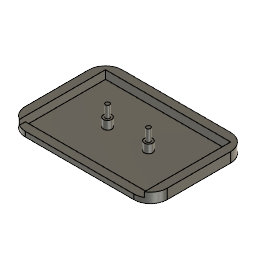
Battery holder cover (Autodesk Fusion 360 design; units mm, degrees)
Autodesk Fusion 360 part; units mm, degrees
sketch "Sketch1" plane through (0, 0, 0) normal (0, 0, 1) x (1, 0, 0)
  line L0 (0, 0) -> (85, 0)
  line L1 (85, 0) -> (85, 58)
  line L2 (85, 58) -> (0, 58)
  line L3 (0, 58) -> (0, 0)
  dimension "d1" = 85
  dimension "d2" = 58
  constraint horizontal L0
  constraint vertical L1
  constraint horizontal L2
  constraint vertical L3
  constraint coincident L0.start L3.end
  measures "d1" distance of L0.start L0.end
  measures "d2" distance of L0.start L2.end
extrude "Extrude1" add sketch "Sketch1" along normal blind 1
fillet "Fillet1" radius 10 4 edges at (85, 0, 0.5) (0, 0, 0.5) (0, 58, 0.5) (85, 58, 0.5)
sketch "Sketch2" plane through (0, 0, 1) normal (0, 0, 1) x (-1, 0, 0)
  arc A0 (-85, -48) -> (-75, -58) centre (-75, -48) ccw
  line L0 (-75, -58) -> (-10, -58)
  arc A1 (-10, -58) -> (0, -48) centre (-10, -48) ccw
  line L1 (0, -48) -> (0, -10)
  arc A2 (0, -10) -> (-10, 0) centre (-10, -10) ccw
  line L2 (-10, 0) -> (-75, 0)
  arc A3 (-75, 0) -> (-85, -10) centre (-75, -10) ccw
  line L3 (-85, -10) -> (-85, -48)
  line L4 (0, -29) -> (-85, -29)
  line L5 (0, -29) -> (-30.25, -29)
  line L6 (-85, -29) -> (-54.75, -29)
  circle A4 centre (-30.25, -29) radius 2.5
  circle A5 centre (-54.75, -29) radius 2.5
  dimension "d7" = 30.25
  dimension "d8" = 30.25
  dimension "d9" = 5
  dimension "d10" = 5
  constraint midpoint L1 L4.start
  constraint midpoint L3 L4.end
  constraint perpendicular L1 L5
  constraint perpendicular L3 L6
  constraint coincident L5.end A4.centre
  constraint coincident L6.end A5.centre
  measures "d7" distance of L4.start L5.end
  measures "d8" distance of L4.end L6.end
  measures "d9" diameter of A4
  measures "d10" diameter of A5
extrude "Extrude2" add sketch "Sketch2" along normal blind 5 contours L4 L6 A5 | L4 L6 A5 | L4 L5 A4 | L4 L5 A4
sketch "Sketch3" plane through (0, 0, 1) normal (0, 0, 1) x (-1, 0, 0)
  circle A0 centre (-54.75, -29) radius 2.5
  circle A1 centre (-30.25, -29) radius 2.5
  arc A2 (-85, -48) -> (-75, -58) centre (-75, -48) ccw
  line L0 (-75, -58) -> (-10, -58)
  arc A3 (-10, -58) -> (0, -48) centre (-10, -48) ccw
  line L1 (0, -48) -> (0, -10)
  arc A4 (0, -10) -> (-10, 0) centre (-10, -10) ccw
  line L2 (-10, 0) -> (-75, 0)
  arc A5 (-75, 0) -> (-85, -10) centre (-75, -10) ccw
  line L3 (-85, -10) -> (-85, -48)
  line L4 (-80, -5) -> (-5, -5)
  line L5 (-5, -5) -> (-5, -53)
  line L6 (-5, -53) -> (-80, -53)
  line L7 (-80, -53) -> (-80, -5)
  line L8 (-80, -5) -> (-5, -53) construction
  line L9 (-5, -5) -> (-80, -53) construction
  point P0 (-42.5, -29)
  constraint horizontal L4
  constraint perpendicular L4 L5
  constraint parallel L4 L6
  constraint parallel L5 L7
  constraint coincident L8 P0
  constraint coincident L9 P0
extrude "Extrude3" add sketch "Sketch3" along normal blind 5 contours A2 L0 A3 L1 A4 L2 A5 L3
sketch "Sketch4" plane through (0, 0, 6) normal (0, 0, 1) x (-1, 0, 0)
  circle A0 centre (-30.25, -29) radius 2.5
  circle A1 centre (-30.25, -29) radius 1.4
  dimension "d15" = 2.8
  constraint concentric A0 A1
  measures "d15" diameter of A1
sketch "Sketch5" plane through (0, 0, 6) normal (0, 0, 1) x (-1, 0, 0)
  circle A0 centre (-54.75, -29) radius 2.5
  circle A1 centre (-54.75, -29) radius 1.4
  dimension "d16" = 2.8
  constraint concentric A0 A1
  measures "d16" diameter of A1
extrude "Extrude4" add sketch "Sketch4" sketch "Sketch5" along normal blind 7 contours A1 of sketch 2 contours A1
sketch "Sketch6" plane through (0, 0, 6) normal (0, 0, 1) x (-1, 0, 0)
  line L0 (-5, -53) -> (-80, -53)
  line L1 (-80, -53) -> (-80, -5)
  line L2 (-80, -5) -> (-5, -5)
  line L3 (-5, -5) -> (-5, -53)
  line L4 (-85, -10) -> (-85, -48)
  arc A0 (-85, -48) -> (-75, -58) centre (-75, -48) ccw
  line L5 (-75, -58) -> (-10, -58)
  arc A1 (-10, -58) -> (0, -48) centre (-10, -48) ccw
  line L6 (0, -48) -> (0, -10)
  arc A2 (0, -10) -> (-10, 0) centre (-10, -10) ccw
  line L7 (-10, 0) -> (-75, 0)
  arc A3 (-75, 0) -> (-85, -10) centre (-75, -10) ccw
  line L8 (-5, -5) -> (-80, -5)
  line L9 (-80, -5) -> (-80, 10)
  line L10 (-80, 10) -> (-5, 10)
  line L11 (-5, 10) -> (-5, -5)
  constraint horizontal L8
  constraint vertical L9
  constraint horizontal L10
  constraint vertical L11
  constraint coincident L2.end L3.start
extrude "Extrude5" cut sketch "Sketch6" against normal blind 3 contours L2 A2 L7 A3 L8 L9 L11
sketch "Sketch7" plane through (0, 0, 13) normal (0, 0, 1) x (-1, 0, 0)
  circle A0 centre (-54.75, -29) radius 1.4
  circle A1 centre (-54.75, -29) radius 1.25
  dimension "d23" = 2.5
  constraint concentric A0 A1
  measures "d23" diameter of A1
sketch "Sketch8" plane through (0, 0, 13) normal (0, 0, 1) x (-1, 0, 0)
  circle A0 centre (-30.25, -29) radius 1.4
  circle A1 centre (-30.25, -29) radius 1.25
  dimension "d24" = 2.5
  constraint concentric A0 A1
  measures "d24" diameter of A1
extrude "Extrude6" cut sketch "Sketch8" sketch "Sketch7" against normal blind 7 of sketch 2
equation "d7 = 28.75 mm + 1.5 mm"
